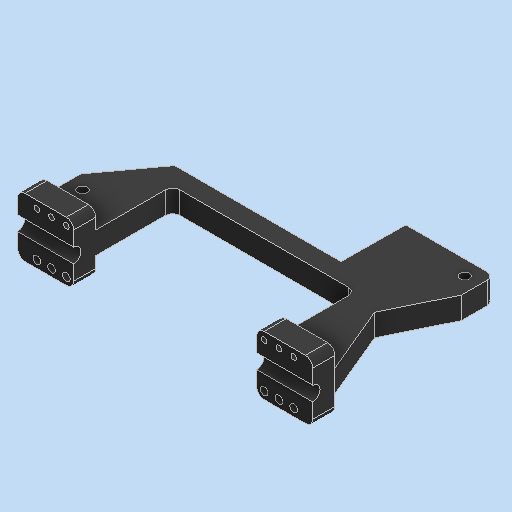
# Autodesk Inventor part: Stabilisatuer2.1
Saved by Autodesk Inventor 2026 (Build 300175050, 175E)
## iProperties
Created: 2025-04-25
Part Number: Stabilisatuer2.1
Material: Gummi
Document SubType Name: Modeling
Designer: karle
Density: 0.93 g/cm^3
Appearance: Gummi - Schwarz
Author: karle
Autodesk Inventor part; units mm, degrees
ref_plane "YZ Plane" through (0, 0, 0) normal (1, 0, 0) x (0, 1, 0)
ref_plane "XZ Plane" through (0, 0, 0) normal (0, 1, 0) x (-1, 0, 0)
ref_plane "XY Plane" through (0, 0, 0) normal (0, 0, 1) x (1, 0, 0)
sketch "Skizze1" plane through (0, 0, 0) normal (0, 0, 1) x (1, 0, 0)
  line L0 (-100, 0) -> (-62, 0)
  line L1 (-62, 0) -> (-62, 67)
  line L2 (-62, 67) -> (62, 67)
  line L3 (62, 67) -> (62, 0)
  line L4 (62, 0) -> (100, 0)
  line L5 (100, 0) -> (100, 123)
  line L6 (100, 123) -> (-100, 123)
  line L7 (-100, 123) -> (-100, 0)
  line L8 (0, 90.2324) -> (0, 0)
  point P0 (81, 0)
  point P1 (0, 77)
  point P2 (0, 67)
  dimension "d0" = 124
  dimension "d1" = 67
  dimension "d2" = 0
  dimension "d3" = 62
  dimension "d4" = 200
  dimension "d5" = 56
  constraints: 18 end point, 6 perpendicular, 2 point on line, 1 horizontal, 1 midpoint, 1 vertical, 1 other
  measures "d0" distance between parallel lines of L1 L3
  measures "d1" distance from line of point (81, 0) L2
  measures "d2" vertical distance of L8.end point (81, 0)
  measures "d3" distance from line of L3 L8.end
  measures "d4" distance between parallel lines of L5 L7
  measures "d5" distance between parallel lines of L6 L2
extrude "Extrusion1" add sketch "Skizze1" along normal mid plane 15
sketch "Skizze2" plane through (-100, 0, 7.5) normal (0, -1, 0) x (1, 0, 0)
  line L0 (0, 12.5) -> (38, 12.5)
  line L1 (38, 12.5) -> (38, -27.5)
  line L2 (38, -27.5) -> (0, -27.5)
  line L3 (0, -27.5) -> (0, 12.5)
  line L4 (162, 12.5) -> (200, 12.5)
  line L5 (200, 12.5) -> (200, -27.5)
  line L6 (200, -27.5) -> (162, -27.5)
  line L7 (162, -27.5) -> (162, 12.5)
  line L8 (200, -15) -> (200, 0) projected
  line L9 (162, -15) -> (162, 0) projected
  line L10 (0, -15) -> (0, 0) projected
  line L11 (38, -15) -> (38, 0) projected
  line L12 (171.2366, -7.5) -> (-10.2497, -7.5)
  point P0 (100, -7.5)
  point P1 (181, -27.5)
  point P2 (181, 12.5)
  point P3 (167, -22.5)
  point P4 (33, -20.9733)
  point P5 (33, 5.9733)
  point P6 (167, 7.5)
  dimension "d8" = 40
  dimension "d9" = 12.5
  dimension "d12" = 30
  dimension "d14" = 5
  dimension "d16" = 5
  constraints: 18 end point, 4 collinear, 4 parallel, 3 horizontal, 2 midpoint, 2 perpendicular, 2 point on line, 2 symmetric about line, 1 other
  measures "d8" distance of point (181, -27.5) point (181, 12.5)
  measures "d9" distance from line of L8.end L0
  measures "d12" distance of point (167, 7.5) point (167, -22.5)
  measures "d14" distance from line of L7 point (167, -22.5)
  measures "d16" distance from line of L1 point (33, -20.973)
extrude "Extrusion2" add sketch "Skizze2" against normal blind 15
sketch "Skizze8" plane through (-100, 0, 20) normal (0, -1, 0) x (1, 0, 0)
  line L0 (0, -40) -> (0, 0) projected
  line L1 (38, 0) -> (0, 0) projected
  line L2 (200, -40) -> (200, 0) projected
  line L3 (162, -40) -> (162, 0) projected
  line L4 (38, -40) -> (38, 0) projected
  point P0 (100, -20)
  point P1 (13, -5)
  point P2 (13, -35)
  point P3 (167, -35)
  point P4 (167, -5)
  point P5 (23, -5)
  point P6 (23, -35)
  point P7 (33, -5)
  point P8 (33, -35)
  point P9 (177, -5)
  point P10 (177, -35)
  point P11 (187, -5)
  point P12 (187, -35)
  dimension "d56" = 30
  dimension "d98" = 5
  dimension "d101" = 10
  dimension "d108" = 10
  dimension "d113" = 5
  constraints: 2 horizontal, 2 horizontal alignment, 2 vertical alignment, 8 other
  measures "d56" distance of point (13, -5) point (13, -35)
  measures "d98" distance from line of L3 point (167, -5)
  measures "d101" distance of point (13, -5) point (23, -5)
  measures "d108" distance of point (167, -5) point (177, -5)
  measures "d113" distance from line of point (33, -5) L4
hole "Bohrung5" at (-87, 0, 15) at (67, 0, 15) at (-77, 0, 15) at (-67, 0, 15) at (77, 0, 15) at (87, 0, 15) direction (0, 1, 0) diameter 3.8 depth 13
hole "Bohrung6" at (-87, 0, -15) at (67, 0, -15) at (77, 0, -15) at (87, 0, -15) at (-77, 0, -15) at (-67, 0, -15) direction (0, 1, 0) diameter 5.2 end through all
fillet "Rundung2" radius 5 8 edges at (62, 7.5, -20) (62, 7.5, 20) (100, 7.5, -20) (100, 7.5, 20) (-62, 7.5, 20) (-100, 7.5, 20) (-100, 7.5, -20) (-62, 7.5, -20)
fillet "Rundung3" radius 5 4 edges at (-62, 67, 0) (-100, 123, 0) (100, 123, 0) (62, 67, 0)
sketch "Skizze9" plane through (100, 0, 15) normal (1, 0, 0) x (0, 0, -1)
  point P0 (15, 0)
  point P1 (15, 0)
  constraints: 1 coincident
hole "Bohrung7" at (100, 0, 0) direction (-1, 0, 0) diameter 9.8 end through all
sketch "Skizze11" plane through (0, 0, 7.5) normal (0, 0, 1) x (1, 0, 0)
  line L0 (95, 123) -> (-95, 123) projected
  line L1 (100, 15) -> (100, 118) projected
  line L2 (-100, 118) -> (-100, 15) projected
  line L3 (-67, 0) -> (-95, 0) projected
  point P0 (0, 0)
  point P1 (90, 113)
  point P2 (-90, 34)
  dimension "d86" = 10
  dimension "d87" = 10
  dimension "d95" = 10
  dimension "d96" = 34
  measures "d86" distance from line of point (90, 113) L0
  measures "d87" distance from line of L1 point (90, 113)
  measures "d95" distance from line of L2 point (-90, 34)
  measures "d96" distance from line of L3 point (-90, 34)
hole "Bohrung8" at (90, 113, 7.5) at (-90, 34, 7.5) direction (0, 0, -1) diameter 6.5 end through all
sketch "Skizze14" plane through (0, 0, 7.5) normal (0, 0, 1) x (1, 0, 0)
  line L0 (-73.1143, 79.5143) -> (39.5639, 79.5143)
  line L1 (-95, 123) -> (95, 123) projected
  line L2 (-100, 123) -> (-100, 42.7976)
  line L3 (-100, 15) -> (-100, 118) projected
  line L4 (-73.1143, 79.5143) -> (-100, 42.7976)
  line L5 (100, 15) -> (100, 118) projected
  line L6 (100, 100.6581) -> (80.6664, 61.1559)
  line L7 (80.6664, 61.1559) -> (100, 15)
  line L8 (100, 15) -> (100, 100.6581)
  line L9 (-100, 123) -> (70.7174, 123)
  line L10 (95, 123) -> (40, 123)
  line L11 (39.5639, 79.5143) -> (40, 123)
  point P0 (0, 0)
  dimension "d118" = 60
  constraints: 18 end point, 4 point on line, 2 collinear, 1 horizontal
  measures "d118" distance from line of L10.end L5
extrude "Extrusion5" cut sketch "Skizze14" against normal through all
